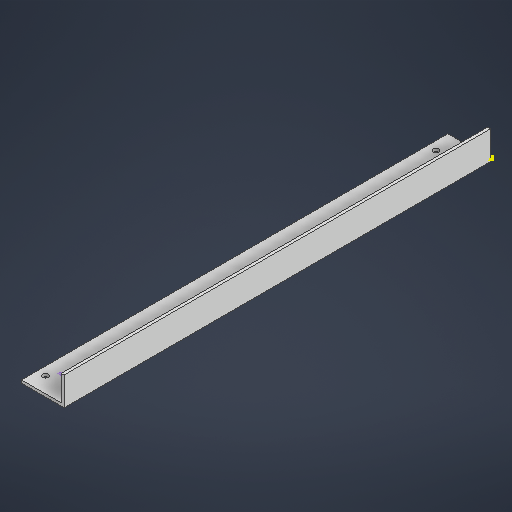
# Autodesk Inventor part: 1_1_2_2_profile_L_G
Saved by Autodesk Inventor 2026 (Build 300175000, 175)
## iProperties
Created: 2025-05-06
Part Number: 1_1_2_2_profile_L_G
Material: Generic
Document SubType Name: Modeling
Designer: remg9
Density: 1 g/cm^3
Appearance: Default
Author: remg9
Autodesk Inventor part; units mm, degrees
ref_plane "YZ Plane" through (0, 0, 0) normal (1, 0, 0) x (0, 1, 0)
ref_plane "XZ Plane" through (0, 0, 0) normal (0, 1, 0) x (-1, 0, 0)
ref_plane "XY Plane" through (0, 0, 0) normal (0, 0, 1) x (1, 0, 0)
sketch "Sketch1" plane through (0, 0, 0) normal (0, 0, 1) x (1, 0, 0)
  line L0 (0, 0) -> (0, 20)
  line L1 (0, 20) -> (-2, 20)
  line L2 (-2, 20) -> (-2, 2)
  line L3 (-2, 2) -> (-30, 2)
  line L4 (-30, 2) -> (-30, 0)
  line L5 (-30, 0) -> (0, 0)
  dimension "d0" = 20
  dimension "d1" = 30
  dimension "d2" = 2
  dimension "d3" = 2
  constraints: 12 end point, 5 perpendicular, 1 vertical
  measures "d0" distance of L0.start L0.end
  measures "d1" distance of L4.end L0.start
  measures "d2" distance of L3.end L4.end
  measures "d3" distance of L0.end L1.end
extrude "Extrusion1" add sketch "Sketch1" along normal blind 300
sketch "Sketch2" plane through (-30, 2, 0) normal (0, 1, 0) x (1, 0, 0)
  line L0 (14, -8.7881) -> (14, -378.1278) construction
  line L1 (70.3933, -289) -> (-76.229, -289) construction
  line L2 (70.3933, -14.5) -> (-70.6611, -14.5) construction
  line L3 (0, 0) -> (0, -300) projected
  line L4 (28, -300) -> (0, -300) projected
  line L5 (28, 0) -> (0, 0) projected
  line L6 (28, 0) -> (28, -300) projected
  point P0 (30, 0)
  point P1 (22, -14.5)
  point P2 (6, -14.5)
  point P3 (14, -33.5)
  point P4 (6, -289)
  point P5 (14, -270)
  point P6 (22, -289)
  dimension "d6" = 14
  dimension "d7" = 11
  dimension "d8" = 14.5
  dimension "d9" = 19
  dimension "d10" = 6
  dimension "d11" = 6
  dimension "d12" = 6
  dimension "d13" = 6
  dimension "d14" = 19
  constraints: 6 end point, 6 point on line, 2 horizontal, 1 vertical
  measures "d6" distance between parallel lines of L3 L0
  measures "d7" distance between parallel lines of L4 L1
  measures "d8" distance between parallel lines of L5 L2
  measures "d9" distance from line of L1 point (14, -270)
  measures "d10" distance from line of L3 point (6, -289)
  measures "d11" distance from line of L6 point (22, -289)
  measures "d12" distance from line of L3 point (6, -14.5)
  measures "d13" distance from line of L6 point (22, -14.5)
  measures "d14" distance from line of L2 point (14, -33.5)
hole "Hole1" at (-8, 2, 14.5) at (-24, 2, 14.5) at (-16, 2, 33.5) at (-24, 2, 289) at (-16, 2, 270) at (-8, 2, 289) direction (0, -1, 0) diameter 4 end through all
sketch "Sketch3" plane through (-30, 2, 0) normal (0, 1, 0) x (1, 0, 0)
  line L0 (10.2266, -19.7088) -> (18.558, -19.7088) construction
  line L1 (18.558, -19.7088) -> (18.558, -23.4953) construction
  line L2 (18.558, -23.4953) -> (10.2266, -23.4953) construction
  line L3 (10.2266, -23.4953) -> (10.2266, -19.7088) construction
  line L4 (8.3546, -280.5692) -> (18.1359, -280.5692) construction
  line L5 (18.1359, -280.5692) -> (18.1359, -286.4282) construction
  line L6 (18.1359, -286.4282) -> (8.3546, -286.4282) construction
  line L7 (8.3546, -286.4282) -> (8.3546, -280.5692) construction
  point P0 (30, 0)
  dimension "d0" = 20
  dimension "d1" = 30
  dimension "d2" = 2
  dimension "d3" = 2
  constraints: 4 other
body "Solid1"
